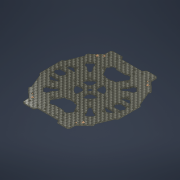
# Autodesk Inventor part: Lower Base fix 2
Saved by Autodesk Inventor 2021 (Build 250183000, 183)
## iProperties
Created: 2021-04-04
Part Number: Lower Base fix 2
Material: Fiberglass Batt
Document SubType Name: Modeling
Designer: ACER
Density: 0.032 g/cm^3
Appearance: Carbon Fiber 1
Author: ACER
Autodesk Inventor part; units mm, degrees
sketch "Sketch1" plane through (0, 0, 0) normal (0, 1, 0) x (-1, 0, 0)
  arc A0 (303.2496, 232.6894) -> (303.2496, 235.8894) centre (303.2496, 234.2894) ccw
  line L0 (323.663, 256.7678) -> (315.419, 242.7086)
  arc A1 (314.1875, 241.9686) -> (315.419, 242.7086) centre (314.125, 243.4673) ccw
  circle A2 centre (320.9996, 225.0394) radius 1.6
  line L1 (314.1875, 241.9686) -> (309.569, 241.7763)
  line L2 (309.569, 241.7763) -> (308.77, 240.8828)
  arc A3 (307.2791, 240.2159) -> (308.77, 240.8828) centre (307.2791, 242.2159) ccw
  line L3 (307.2791, 240.2159) -> (303.2192, 240.2159)
  line L4 (314.2761, 265.6643) -> (317.6382, 265.6643)
  arc A4 (314.2761, 265.6643) -> (312.529, 264.8601) centre (314.2761, 263.3643) ccw
  line L5 (303.2192, 263.7806) -> (311.6046, 263.7806)
  line L6 (311.6046, 263.7806) -> (312.529, 264.8601)
  arc A5 (332.5996, 207.2894) -> (329.3996, 207.2894) centre (330.9996, 207.2894) ccw
  line L7 (352.3567, 213.4142) -> (363.3075, 213.4142)
  line L8 (350.9567, 210.9441) -> (350.9567, 212.0142)
  line L9 (364.7075, 212.0142) -> (364.7075, 210.8124)
  line L10 (364.7075, 210.8124) -> (366.1742, 209.8202)
  line L11 (349.4293, 209.7993) -> (350.9567, 210.9441)
  arc A6 (366.7898, 208.6606) -> (366.1742, 209.8202) centre (365.3898, 208.6606) ccw
  line L12 (366.7898, 208.6606) -> (366.7898, 207.2894)
  arc A7 (349.4293, 209.7993) -> (348.8689, 208.679) centre (350.2689, 208.679) ccw
  line L13 (348.8689, 207.2894) -> (348.8689, 208.679)
  arc A8 (346.3456, 207.2894) -> (344.1536, 207.2894) centre (345.2496, 207.2894) ccw
  arc A9 (352.3567, 213.4142) -> (350.9567, 212.0142) centre (352.3567, 212.0142) ccw
  circle A10 centre (325.2496, 253.2894) radius 1.5
  arc A11 (323.663, 256.7678) -> (323.5245, 259.3038) centre (321.679, 257.9312) ccw
  line L14 (319.4837, 264.7369) -> (323.5245, 259.3038)
  arc A12 (319.4837, 264.7369) -> (317.6382, 265.6643) centre (317.6382, 263.3643) ccw
  line L15 (338.5006, 237.402) -> (338.4992, 237.3504)
  arc A13 (344.0065, 240.2975) -> (345.0316, 240.2557) centre (344.5587, 241.2489) ccw
  arc A14 (344.0065, 240.2975) -> (343.3339, 240.3141) centre (343.6551, 239.6921) ccw
  line L16 (343.3339, 240.3141) -> (338.8786, 238.0137)
  arc A15 (338.8786, 238.0137) -> (338.4997, 237.3913) centre (339.1997, 237.3917) ccw
  arc A16 (337.6845, 236.0559) -> (338.4997, 237.3913) centre (336.9997, 237.3905) ccw
  line L17 (337.6845, 236.0559) -> (333.2693, 233.7905)
  arc A17 (330.511, 234.5509) -> (330.7655, 234.3663) centre (331.2181, 235.258) ccw
  line L18 (331.9055, 233.7876) -> (330.7655, 234.3663)
  arc A18 (331.9055, 233.7876) -> (333.2693, 233.7905) centre (332.5845, 235.1251) ccw
  circle A19 centre (349.2496, 266.0394) radius 1.5
  circle A20 centre (342.7496, 272.2894) radius 1.5
  line L19 (345.8396, 249.7893) -> (348.5507, 247.0628)
  arc A21 (348.9285, 245.7899) -> (348.5507, 247.0628) centre (347.558, 246.0756) ccw
  line L20 (348.9285, 245.7899) -> (348.1581, 242.0944)
  arc A22 (347.7189, 241.5354) -> (348.1581, 242.0944) centre (347.375, 242.2577) ccw
  line L21 (347.7189, 241.5354) -> (345.0316, 240.2557)
  circle A23 centre (364.7496, 215.5394) radius 1.6
  arc A24 (364.7075, 212.0142) -> (363.3075, 213.4142) centre (363.3075, 212.0142) ccw
  circle A25 centre (349.2496, 229.2894) radius 1.5
  arc A26 (345.5474, 223.4422) -> (346.3385, 220.4514) centre (346.3385, 222.0514) ccw
  line L22 (346.3385, 220.4514) -> (360.2389, 220.4514)
  arc A27 (360.2389, 220.4514) -> (361.2146, 223.3195) centre (360.2389, 222.0514) ccw
  line L23 (353.0198, 227.6924) -> (345.5474, 223.4422)
  arc A28 (355.7803, 227.5007) -> (353.0198, 227.6924) centre (354.2558, 225.5193) ccw
  line L24 (361.2146, 223.3195) -> (355.7803, 227.5007)
  circle A29 centre (371.2496, 218.2894) radius 1.35
  circle A30 centre (318.9996, 271.2894) radius 1.5
  circle A31 centre (326.2496, 279.2894) radius 1.5
  circle A32 centre (313.2496, 278.5394) radius 1.5
  circle A33 centre (340.2496, 279.2894) radius 1.5
  line L25 (322.7496, 288.2894) -> (342.7496, 288.2894) construction
  arc A34 (307.2496, 207.2894) -> (303.2496, 211.2894) centre (303.2496, 207.2894) ccw
  arc A35 (310.6109, 212.4674) -> (308.4393, 214.6424) centre (303.2496, 207.2894) ccw
  arc A36 (322.7299, 215.1328) -> (311.2084, 226.7229) centre (303.2496, 207.2894) ccw
  line L26 (320.7332, 211.9779) -> (312.629, 211.4948)
  line L27 (307.4713, 216.6838) -> (308.0424, 224.7567)
  arc A37 (310.6109, 212.4674) -> (312.629, 211.4948) centre (312.4921, 213.7907) ccw
  arc A38 (307.4713, 216.6838) -> (308.4393, 214.6424) centre (309.7656, 216.5215) ccw
  arc A39 (311.2084, 226.7229) -> (308.0424, 224.7567) centre (310.3367, 224.5944) ccw
  arc A40 (320.7332, 211.9779) -> (322.7299, 215.1328) centre (320.5963, 214.2738) ccw
  line L28 (303.2496, 207.2894) -> (330.9996, 207.2894)
  line L29 (320.9996, 207.2894) -> (320.9996, 205.9182)
  line L30 (320.9996, 207.2894) -> (320.9996, 225.0394)
  line L31 (320.9996, 225.0394) -> (303.2496, 225.0394)
  line L32 (303.2496, 234.2894) -> (303.2496, 207.2894)
  line L33 (303.2496, 207.2894) -> (374.7496, 207.2894)
  line L34 (303.2496, 207.2894) -> (303.2496, 283.2894)
  line L35 (303.2496, 207.2894) -> (379.2496, 207.2894) construction
  line L36 (303.2496, 283.2894) -> (303.2496, 288.2894)
  line L37 (303.2496, 283.2894) -> (308.2496, 283.2894) construction
  line L38 (325.2496, 288.2894) -> (322.2496, 283.2894)
  line L39 (325.2496, 288.2894) -> (345.2496, 288.2894)
  line L40 (345.2496, 288.2894) -> (345.2496, 276.2894)
  line L41 (352.9139, 268.8587) -> (346.4139, 275.1087)
  line L42 (345.2496, 276.2894) -> (363.2694, 258.9607)
  line L43 (345.2496, 276.2894) -> (370.2496, 276.2894) construction
  line L44 (363.2694, 258.9607) -> (360.4968, 256.0775)
  line L45 (374.7496, 207.2894) -> (374.7496, 228.7894)
  line L46 (374.7496, 228.7894) -> (371.7496, 228.7894)
  line L47 (371.7496, 228.7894) -> (360.4968, 256.0775)
  line L48 (303.2496, 207.2894) -> (320.9996, 225.0394)
  line L49 (303.2496, 207.2894) -> (328.3519, 207.2894) construction
  line L50 (303.2496, 207.2894) -> (389.5844, 207.2894) construction
  line L51 (345.7947, 249.8345) -> (345.8396, 249.7893)
  line L52 (336.2743, 247.3737) -> (333.9739, 242.9184)
  arc A41 (333.3515, 242.5395) -> (333.9739, 242.9184) centre (333.3519, 243.2395) ccw
  line L53 (333.3622, 242.5404) -> (333.3106, 242.539)
  arc A42 (333.3515, 242.5395) -> (332.0161, 241.7243) centre (333.3507, 241.0395) ccw
  arc A43 (330.3265, 234.8053) -> (330.511, 234.5509) centre (331.2181, 235.258) ccw
  line L54 (329.7477, 235.9453) -> (330.3265, 234.8053)
  arc A44 (329.7507, 237.3091) -> (329.7477, 235.9453) centre (331.0853, 236.6243) ccw
  line L55 (332.0161, 241.7243) -> (329.7507, 237.3091)
  arc A45 (336.2159, 249.0714) -> (336.2577, 248.0463) centre (337.2091, 248.5985) ccw
  arc A46 (336.2743, 247.3737) -> (336.2577, 248.0463) centre (335.6523, 247.6949) ccw
  line L56 (345.7495, 249.8794) -> (343.023, 252.5905)
  arc A47 (343.023, 252.5905) -> (341.7501, 252.9683) centre (342.0358, 251.5978) ccw
  line L57 (341.7501, 252.9683) -> (338.0546, 252.1979)
  arc A48 (338.0546, 252.1979) -> (337.4956, 251.7587) centre (338.2179, 251.4148) ccw
  line L58 (337.4956, 251.7587) -> (336.2159, 249.0714)
  line L59 (345.7947, 249.8345) -> (345.7495, 249.8794)
  line L60 (303.2496, 283.2894) -> (322.2496, 283.2894)
  line L61 (303.2496, 283.2894) -> (322.2496, 283.2894)
  line L62 (322.2496, 283.2894) -> (325.2496, 288.2894)
  line L63 (325.2496, 288.2894) -> (345.2496, 288.2894)
  line L64 (345.2496, 288.2894) -> (345.2496, 276.2894)
  line L65 (345.2496, 276.2894) -> (363.2694, 258.9607)
  line L66 (363.2694, 258.9607) -> (360.4968, 256.0775)
  line L67 (360.4968, 256.0775) -> (371.7496, 228.7894)
  line L68 (371.7496, 228.7894) -> (374.7496, 228.7894)
  line L69 (374.7496, 228.7894) -> (374.7496, 207.2894)
  line L70 (374.7496, 207.2894) -> (303.2496, 207.2894)
  arc A49 (124.9548, 185.5697) -> (124.3945, 184.4495) centre (125.7945, 184.4495) ccw
  line L71 (124.3945, 183.0599) -> (124.3945, 184.4495)
  arc A50 (121.8711, 183.0599) -> (119.6792, 183.0599) centre (120.7752, 183.0599) ccw
  line L72 (140.2331, 187.7846) -> (140.2331, 186.5829)
  line L73 (140.2331, 186.5829) -> (141.6998, 185.5907)
  circle A51 centre (140.2752, 191.3099) radius 1.6
  arc A52 (140.2331, 187.7846) -> (138.8331, 189.1846) centre (138.8331, 187.7846) ccw
  arc A53 (142.3153, 184.4311) -> (141.6998, 185.5907) centre (140.9153, 184.4311) ccw
  circle A54 centre (146.7752, 194.0599) radius 1.35
  line L74 (142.3153, 184.4311) -> (142.3153, 183.0599)
  line L75 (127.8822, 189.1846) -> (138.8331, 189.1846)
  line L76 (126.4822, 186.7146) -> (126.4822, 187.7846)
  line L77 (124.9548, 185.5697) -> (126.4822, 186.7146)
  arc A55 (135.7645, 196.2219) -> (136.7402, 199.09) centre (135.7645, 197.8219) ccw
  arc A56 (127.8822, 189.1846) -> (126.4822, 187.7846) centre (127.8822, 187.7846) ccw
  line L78 (136.7402, 199.09) -> (131.3058, 203.2711)
  arc A57 (131.3058, 203.2711) -> (128.5453, 203.4628) centre (129.7814, 201.2897) ccw
  line L79 (121.864, 196.2219) -> (135.7645, 196.2219)
  arc A58 (121.073, 199.2126) -> (121.864, 196.2219) centre (121.864, 197.8219) ccw
  line L80 (128.5453, 203.4628) -> (121.073, 199.2126)
  circle A59 centre (124.7752, 205.0599) radius 1.5
  circle A60 centre (96.5252, 200.8099) radius 1.6
  line L81 (118.8595, 216.0846) -> (114.4041, 213.7841)
  arc A61 (114.4041, 213.7841) -> (114.0253, 213.1618) centre (114.7253, 213.1622) ccw
  line L82 (114.0261, 213.1725) -> (114.0247, 213.1209)
  arc A62 (113.21, 211.8264) -> (114.0253, 213.1618) centre (112.5253, 213.1609) ccw
  arc A63 (106.0366, 210.3213) -> (106.2911, 210.1367) centre (106.7437, 211.0284) ccw
  line L83 (107.4311, 209.558) -> (106.2911, 210.1367)
  arc A64 (107.4311, 209.558) -> (108.7948, 209.561) centre (108.1101, 210.8955) ccw
  line L84 (113.21, 211.8264) -> (108.7948, 209.561)
  arc A65 (78.7752, 208.4599) -> (78.7752, 211.6599) centre (78.7752, 210.0599) ccw
  arc A66 (89.713, 217.7391) -> (90.9446, 218.479) centre (89.6506, 219.2378) ccw
  line L85 (89.713, 217.7391) -> (85.0945, 217.5467)
  line L86 (85.0945, 217.5467) -> (84.2956, 216.6532)
  arc A67 (82.8047, 215.9864) -> (84.2956, 216.6532) centre (82.8047, 217.9864) ccw
  line L87 (82.8047, 215.9864) -> (78.7448, 215.9864)
  arc A68 (119.532, 216.068) -> (120.5572, 216.0262) centre (120.0842, 217.0193) ccw
  arc A69 (119.532, 216.068) -> (118.8595, 216.0846) centre (119.1806, 215.4626) ccw
  circle A70 centre (124.7752, 241.8099) radius 1.5
  line L88 (121.3651, 225.5598) -> (124.0763, 222.8332)
  arc A71 (124.4541, 221.5604) -> (124.0763, 222.8332) centre (123.0835, 221.8461) ccw
  line L89 (124.4541, 221.5604) -> (123.6837, 217.8649)
  arc A72 (123.2445, 217.3059) -> (123.6837, 217.8649) centre (122.9005, 218.0281) ccw
  line L90 (123.2445, 217.3059) -> (120.5572, 216.0262)
  line L91 (99.1886, 232.5383) -> (90.9446, 218.479)
  arc A73 (95.0093, 240.5073) -> (93.1637, 241.4347) centre (93.1637, 239.1347) ccw
  line L92 (89.8016, 241.4347) -> (93.1637, 241.4347)
  line L93 (95.0093, 240.5073) -> (99.0501, 235.0743)
  arc A74 (99.1886, 232.5383) -> (99.0501, 235.0743) centre (97.2045, 233.7017) ccw
  circle A75 centre (100.7752, 229.0599) radius 1.5
  line L94 (87.1302, 239.551) -> (88.0545, 240.6306)
  arc A76 (89.8016, 241.4347) -> (88.0545, 240.6306) centre (89.8016, 239.1347) ccw
  circle A77 centre (94.5252, 247.0599) radius 1.5
  circle A78 centre (101.7752, 255.0599) radius 1.5
  circle A79 centre (118.2752, 248.0599) radius 1.5
  circle A80 centre (115.7752, 255.0599) radius 1.5
  line L95 (78.7448, 239.551) -> (87.1302, 239.551)
  circle A81 centre (88.7752, 254.3099) radius 1.5
  arc A82 (86.1364, 188.2379) -> (83.9649, 190.4129) centre (78.7752, 183.0599) ccw
  arc A83 (98.2554, 190.9033) -> (86.7339, 202.4933) centre (78.7752, 183.0599) ccw
  line L96 (96.2587, 187.7483) -> (88.1545, 187.2652)
  line L97 (82.9969, 192.4543) -> (83.568, 200.5272)
  arc A84 (86.1364, 188.2379) -> (88.1545, 187.2652) centre (88.0177, 189.5611) ccw
  arc A85 (82.9969, 192.4543) -> (83.9649, 190.4129) centre (85.2912, 192.292) ccw
  arc A86 (86.7339, 202.4933) -> (83.568, 200.5272) centre (85.8622, 200.3649) ccw
  arc A87 (96.2587, 187.7483) -> (98.2554, 190.9033) centre (96.1219, 190.0442) ccw
  line L98 (121.3203, 225.605) -> (121.3651, 225.5598)
  line L99 (121.3203, 225.605) -> (121.2751, 225.6499)
  line L100 (121.2751, 225.6499) -> (118.5485, 228.361)
  line L101 (117.2757, 228.7388) -> (113.5802, 227.9684)
  arc A88 (118.5485, 228.361) -> (117.2757, 228.7388) centre (117.5614, 227.3682) ccw
  arc A89 (111.7415, 224.8419) -> (111.7833, 223.8167) centre (112.7346, 224.3689) ccw
  arc A90 (111.7998, 223.1442) -> (111.7833, 223.8167) centre (111.1779, 223.4653) ccw
  arc A91 (113.5802, 227.9684) -> (113.0212, 227.5292) centre (113.7434, 227.1852) ccw
  line L102 (113.0212, 227.5292) -> (111.7415, 224.8419)
  line L103 (111.7998, 223.1442) -> (109.4994, 218.6888)
  arc A92 (108.8771, 218.31) -> (109.4994, 218.6888) centre (108.8774, 219.01) ccw
  line L104 (108.8878, 218.3108) -> (108.8362, 218.3094)
  arc A93 (108.8771, 218.31) -> (107.5416, 217.4947) centre (108.8762, 216.81) ccw
  line L105 (107.5416, 217.4947) -> (105.2763, 213.0795)
  arc A94 (105.2763, 213.0795) -> (105.2733, 211.7158) centre (106.6108, 212.3948) ccw
  line L106 (105.2733, 211.7158) -> (105.852, 210.5758)
  arc A95 (105.852, 210.5758) -> (106.0366, 210.3213) centre (106.7437, 211.0284) ccw
  line L107 (78.7752, 259.0599) -> (97.7752, 259.0599)
  line L108 (97.7752, 259.0599) -> (100.7752, 264.0599)
  line L109 (100.7752, 264.0599) -> (120.7752, 264.0599)
  line L110 (120.7752, 264.0599) -> (120.7752, 252.0599)
  line L111 (120.7752, 252.0599) -> (138.795, 234.7311)
  line L112 (138.795, 234.7311) -> (136.0224, 231.8479)
  line L113 (136.0224, 231.8479) -> (147.2752, 204.5599)
  line L114 (147.2752, 204.5599) -> (150.2752, 204.5599)
  line L115 (150.2752, 204.5599) -> (150.2752, 183.0599)
  arc A96 (108.1252, 183.0599) -> (104.9252, 183.0599) centre (106.5252, 183.0599) ccw
  line L116 (127.8822, 176.9351) -> (138.8331, 176.9351)
  line L117 (121.864, 169.8979) -> (135.7645, 169.8979)
  arc A97 (126.4822, 178.3351) -> (127.8822, 176.9351) centre (127.8822, 178.3351) ccw
  line L118 (126.4822, 179.4051) -> (126.4822, 178.3351)
  arc A98 (124.3945, 181.6703) -> (124.9548, 180.55) centre (125.7945, 181.6703) ccw
  line L119 (124.3945, 183.0599) -> (124.3945, 181.6703)
  line L120 (124.9548, 180.55) -> (126.4822, 179.4051)
  line L121 (140.2331, 178.3351) -> (140.2331, 179.5369)
  arc A99 (138.8331, 176.9351) -> (140.2331, 178.3351) centre (138.8331, 178.3351) ccw
  line L122 (142.3153, 181.6887) -> (142.3153, 183.0599)
  line L123 (140.2331, 179.5369) -> (141.6998, 180.5291)
  circle A100 centre (140.2752, 174.8099) radius 1.6
  circle A101 centre (146.7752, 172.0599) radius 1.35
  arc A102 (141.6998, 180.5291) -> (142.3153, 181.6887) centre (140.9153, 181.6887) ccw
  arc A103 (78.7752, 154.4599) -> (78.7752, 157.6599) centre (78.7752, 156.0599) ccw
  arc A104 (90.9446, 147.6407) -> (89.713, 148.3807) centre (89.6506, 146.882) ccw
  arc A105 (83.568, 165.5926) -> (86.7339, 163.6264) centre (85.8622, 165.7549) ccw
  line L124 (82.8047, 150.1334) -> (78.7448, 150.1334)
  line L125 (89.713, 148.3807) -> (85.0945, 148.573)
  arc A106 (84.2956, 149.4665) -> (82.8047, 150.1334) centre (82.8047, 148.1334) ccw
  line L126 (85.0945, 148.573) -> (84.2956, 149.4665)
  line L127 (136.7402, 167.0298) -> (131.3058, 162.8486)
  arc A107 (128.5453, 162.6569) -> (131.3058, 162.8486) centre (129.7814, 164.83) ccw
  arc A108 (121.864, 169.8979) -> (121.073, 166.9071) centre (121.864, 168.2979) ccw
  line L128 (128.5453, 162.6569) -> (121.073, 166.9071)
  circle A109 centre (124.7752, 161.0599) radius 1.5
  line L129 (121.3651, 140.56) -> (124.0763, 143.2865)
  arc A110 (118.8595, 150.0352) -> (119.532, 150.0518) centre (119.1806, 150.6572) ccw
  line L130 (124.4541, 144.5594) -> (123.6837, 148.2549)
  arc A111 (120.5572, 150.0936) -> (119.532, 150.0518) centre (120.0842, 149.1004) ccw
  arc A112 (123.6837, 148.2549) -> (123.2445, 148.8139) centre (122.9005, 148.0916) ccw
  line L131 (123.2445, 148.8139) -> (120.5572, 150.0936)
  line L132 (99.1886, 133.5815) -> (90.9446, 147.6407)
  circle A113 centre (100.7752, 137.0599) radius 1.5
  arc A114 (99.0501, 131.0455) -> (99.1886, 133.5815) centre (97.2045, 132.4181) ccw
  line L133 (95.0093, 125.6124) -> (99.0501, 131.0455)
  arc A115 (93.1637, 124.685) -> (95.0093, 125.6124) centre (93.1637, 126.985) ccw
  line L134 (89.8016, 124.685) -> (93.1637, 124.685)
  line L135 (78.7448, 126.5687) -> (87.1302, 126.5687)
  line L136 (87.1302, 126.5687) -> (88.0545, 125.4892)
  arc A116 (88.0545, 125.4892) -> (89.8016, 124.685) centre (89.8016, 126.985) ccw
  circle A117 centre (94.5252, 119.0599) radius 1.5
  circle A118 centre (88.7752, 111.8099) radius 1.5
  circle A119 centre (96.5252, 165.3099) radius 1.6
  line L137 (82.9969, 173.6655) -> (83.568, 165.5926)
  arc A120 (83.9649, 175.7069) -> (82.9969, 173.6655) centre (85.2912, 173.8278) ccw
  arc A121 (83.9649, 175.7069) -> (86.1364, 177.8819) centre (78.7752, 183.0599) ccw
  arc A122 (88.1545, 178.8545) -> (86.1364, 177.8819) centre (88.0177, 176.5586) ccw
  arc A123 (86.7339, 163.6264) -> (98.2554, 175.2165) centre (78.7752, 183.0599) ccw
  arc A124 (119.6792, 183.0599) -> (121.8711, 183.0599) centre (120.7752, 183.0599) ccw
  arc A125 (98.2554, 175.2165) -> (96.2587, 178.3714) centre (96.1219, 176.0755) ccw
  line L138 (96.2587, 178.3714) -> (88.1545, 178.8545)
  arc A126 (114.0253, 152.958) -> (114.4041, 152.3356) centre (114.7253, 152.9576) ccw
  line L139 (114.0261, 152.9473) -> (114.0247, 152.9988)
  arc A127 (114.0253, 152.958) -> (113.21, 154.2934) centre (112.5253, 152.9588) ccw
  arc A128 (106.2911, 155.983) -> (106.0366, 155.7984) centre (106.7437, 155.0913) ccw
  line L140 (107.4311, 156.5617) -> (106.2911, 155.983)
  arc A129 (108.7948, 156.5588) -> (107.4311, 156.5617) centre (108.1101, 155.2242) ccw
  line L141 (113.21, 154.2934) -> (108.7948, 156.5588)
  arc A130 (105.2733, 154.404) -> (105.2763, 153.0402) centre (106.6108, 153.725) ccw
  arc A131 (106.0366, 155.7984) -> (105.852, 155.544) centre (106.7437, 155.0913) ccw
  line L142 (105.2733, 154.404) -> (105.852, 155.544)
  line L143 (107.5416, 148.625) -> (105.2763, 153.0402)
  arc A132 (136.7402, 167.0298) -> (135.7645, 169.8979) centre (135.7645, 168.2979) ccw
  line L144 (121.3203, 140.5148) -> (121.3651, 140.56)
  line L145 (121.3203, 140.5148) -> (121.2751, 140.4699)
  line L146 (118.8595, 150.0352) -> (114.4041, 152.3356)
  line L147 (121.2751, 140.4699) -> (118.5485, 137.7588)
  arc A133 (107.5416, 148.625) -> (108.8771, 147.8098) centre (108.8762, 149.3098) ccw
  arc A134 (109.4994, 147.4309) -> (108.8771, 147.8098) centre (108.8774, 147.1098) ccw
  line L148 (108.8878, 147.8089) -> (108.8362, 147.8103)
  arc A135 (117.2757, 137.381) -> (118.5485, 137.7588) centre (117.5614, 138.7515) ccw
  line L149 (117.2757, 137.381) -> (113.5802, 138.1514)
  circle A136 centre (101.7752, 111.0599) radius 1.5
  circle A137 centre (115.7752, 111.0599) radius 1.5
  circle A138 centre (124.7752, 124.3099) radius 1.5
  arc A139 (124.0763, 143.2865) -> (124.4541, 144.5594) centre (123.0835, 144.2736) ccw
  circle A140 centre (118.2752, 118.0599) radius 1.5
  line L150 (111.7998, 142.9756) -> (109.4994, 147.4309)
  arc A141 (111.7833, 142.303) -> (111.7998, 142.9756) centre (111.1779, 142.6544) ccw
  arc A142 (111.7833, 142.303) -> (111.7415, 141.2779) centre (112.7346, 141.7508) ccw
  line L151 (113.0212, 138.5906) -> (111.7415, 141.2779)
  arc A143 (113.0212, 138.5906) -> (113.5802, 138.1514) centre (113.7434, 138.9345) ccw
  line L152 (78.7752, 107.0599) -> (97.7752, 107.0599)
  line L153 (97.7752, 107.0599) -> (100.7752, 102.0599)
  line L154 (100.7752, 102.0599) -> (120.7752, 102.0599)
  line L155 (120.7752, 102.0599) -> (120.7752, 114.0599)
  line L156 (120.7752, 114.0599) -> (138.795, 131.3886)
  line L157 (138.795, 131.3886) -> (136.0224, 134.2718)
  line L158 (136.0224, 134.2718) -> (147.2752, 161.5599)
  line L159 (147.2752, 161.5599) -> (150.2752, 161.5599)
  line L160 (150.2752, 161.5599) -> (150.2752, 183.0599)
  arc A144 (104.9252, 183.0599) -> (108.1252, 183.0599) centre (106.5252, 183.0599) ccw
  line L161 (29.6681, 189.1846) -> (18.7172, 189.1846)
  line L162 (35.6863, 196.2219) -> (21.7858, 196.2219)
  arc A145 (31.0681, 187.7846) -> (29.6681, 189.1846) centre (29.6681, 187.7846) ccw
  line L163 (31.0681, 186.7146) -> (31.0681, 187.7846)
  arc A146 (33.1558, 184.4495) -> (32.5955, 185.5697) centre (31.7558, 184.4495) ccw
  line L164 (33.1558, 183.0599) -> (33.1558, 184.4495)
  line L165 (32.5955, 185.5697) -> (31.0681, 186.7146)
  line L166 (17.3172, 187.7846) -> (17.3172, 186.5829)
  arc A147 (18.7172, 189.1846) -> (17.3172, 187.7846) centre (18.7172, 187.7846) ccw
  line L167 (15.235, 184.4311) -> (15.235, 183.0599)
  line L168 (17.3172, 186.5829) -> (15.8505, 185.5907)
  circle A148 centre (17.2752, 191.3099) radius 1.6
  circle A149 centre (10.7752, 194.0599) radius 1.35
  arc A150 (15.8505, 185.5907) -> (15.235, 184.4311) centre (16.635, 184.4311) ccw
  arc A151 (78.7752, 211.6599) -> (78.7752, 208.4599) centre (78.7752, 210.0599) ccw
  arc A152 (66.6058, 218.479) -> (67.8373, 217.7391) centre (67.8997, 219.2378) ccw
  arc A153 (73.9823, 200.5272) -> (70.8164, 202.4933) centre (71.6881, 200.3649) ccw
  line L169 (74.7456, 215.9864) -> (78.8055, 215.9864)
  line L170 (67.8373, 217.7391) -> (72.4558, 217.5467)
  arc A154 (73.2547, 216.6532) -> (74.7456, 215.9864) centre (74.7456, 217.9864) ccw
  line L171 (72.4558, 217.5467) -> (73.2547, 216.6532)
  line L172 (20.8102, 199.09) -> (26.2445, 203.2711)
  arc A155 (29.005, 203.4628) -> (26.2445, 203.2711) centre (27.769, 201.2897) ccw
  arc A156 (35.6863, 196.2219) -> (36.4774, 199.2126) centre (35.6863, 197.8219) ccw
  line L173 (29.005, 203.4628) -> (36.4774, 199.2126)
  circle A157 centre (32.7752, 205.0599) radius 1.5
  line L174 (36.1852, 225.5598) -> (33.474, 222.8332)
  arc A158 (38.6908, 216.0846) -> (38.0183, 216.068) centre (38.3697, 215.4626) ccw
  line L175 (33.0963, 221.5604) -> (33.8666, 217.8649)
  arc A159 (36.9931, 216.0262) -> (38.0183, 216.068) centre (37.4661, 217.0193) ccw
  arc A160 (33.8666, 217.8649) -> (34.3058, 217.3059) centre (34.6498, 218.0281) ccw
  line L176 (34.3058, 217.3059) -> (36.9931, 216.0262)
  line L177 (58.3617, 232.5383) -> (66.6058, 218.479)
  circle A161 centre (56.7752, 229.0599) radius 1.5
  arc A162 (58.5002, 235.0743) -> (58.3617, 232.5383) centre (60.3458, 233.7017) ccw
  line L178 (62.541, 240.5073) -> (58.5002, 235.0743)
  arc A163 (64.3866, 241.4347) -> (62.541, 240.5073) centre (64.3866, 239.1347) ccw
  line L179 (67.7487, 241.4347) -> (64.3866, 241.4347)
  line L180 (78.8055, 239.551) -> (70.4201, 239.551)
  line L181 (70.4201, 239.551) -> (69.4958, 240.6306)
  arc A164 (69.4958, 240.6306) -> (67.7487, 241.4347) centre (67.7487, 239.1347) ccw
  circle A165 centre (63.0252, 247.0599) radius 1.5
  circle A166 centre (68.7752, 254.3099) radius 1.5
  circle A167 centre (61.0252, 200.8099) radius 1.6
  line L182 (74.5534, 192.4543) -> (73.9823, 200.5272)
  arc A168 (73.5854, 190.4129) -> (74.5534, 192.4543) centre (72.2591, 192.292) ccw
  arc A169 (73.5854, 190.4129) -> (71.4139, 188.2379) centre (78.7752, 183.0599) ccw
  arc A170 (69.3958, 187.2652) -> (71.4139, 188.2379) centre (69.5327, 189.5611) ccw
  arc A171 (70.8164, 202.4933) -> (59.2949, 190.9033) centre (78.7752, 183.0599) ccw
  arc A172 (37.8711, 183.0599) -> (35.6792, 183.0599) centre (36.7752, 183.0599) ccw
  arc A173 (59.2949, 190.9033) -> (61.2916, 187.7483) centre (61.4284, 190.0442) ccw
  line L183 (61.2916, 187.7483) -> (69.3958, 187.2652)
  arc A174 (43.525, 213.1618) -> (43.1462, 213.7841) centre (42.825, 213.1622) ccw
  line L184 (43.5242, 213.1725) -> (43.5256, 213.1209)
  arc A175 (43.525, 213.1618) -> (44.3403, 211.8264) centre (45.025, 213.1609) ccw
  arc A176 (51.2593, 210.1367) -> (51.5137, 210.3213) centre (50.8066, 211.0284) ccw
  line L185 (50.1192, 209.558) -> (51.2593, 210.1367)
  arc A177 (48.7555, 209.561) -> (50.1192, 209.558) centre (49.4403, 210.8955) ccw
  line L186 (44.3403, 211.8264) -> (48.7555, 209.561)
  arc A178 (52.277, 211.7158) -> (52.2741, 213.0795) centre (50.9395, 212.3948) ccw
  arc A179 (51.5137, 210.3213) -> (51.6983, 210.5758) centre (50.8066, 211.0284) ccw
  line L187 (52.277, 211.7158) -> (51.6983, 210.5758)
  line L188 (50.0087, 217.4947) -> (52.2741, 213.0795)
  arc A180 (20.8102, 199.09) -> (21.7858, 196.2219) centre (21.7858, 197.8219) ccw
  line L189 (36.2301, 225.605) -> (36.1852, 225.5598)
  line L190 (36.2301, 225.605) -> (36.2753, 225.6499)
  line L191 (38.6908, 216.0846) -> (43.1462, 213.7841)
  line L192 (36.2753, 225.6499) -> (39.0018, 228.361)
  arc A181 (50.0087, 217.4947) -> (48.6733, 218.31) centre (48.6741, 216.81) ccw
  arc A182 (48.0509, 218.6888) -> (48.6733, 218.31) centre (48.6729, 219.01) ccw
  line L193 (48.6625, 218.3108) -> (48.7141, 218.3094)
  arc A183 (40.2746, 228.7388) -> (39.0018, 228.361) centre (39.9889, 227.3682) ccw
  line L194 (40.2746, 228.7388) -> (43.9701, 227.9684)
  circle A184 centre (55.7752, 255.0599) radius 1.5
  circle A185 centre (41.7752, 255.0599) radius 1.5
  circle A186 centre (32.7752, 241.8099) radius 1.5
  arc A187 (33.474, 222.8332) -> (33.0963, 221.5604) centre (34.4668, 221.8461) ccw
  circle A188 centre (39.2752, 248.0599) radius 1.5
  line L195 (45.7505, 223.1442) -> (48.0509, 218.6888)
  arc A189 (45.7671, 223.8167) -> (45.7505, 223.1442) centre (46.3725, 223.4653) ccw
  arc A190 (45.7671, 223.8167) -> (45.8088, 224.8419) centre (44.8157, 224.3689) ccw
  line L196 (44.5292, 227.5292) -> (45.8088, 224.8419)
  arc A191 (44.5292, 227.5292) -> (43.9701, 227.9684) centre (43.8069, 227.1852) ccw
  line L197 (78.7752, 259.0599) -> (59.7752, 259.0599)
  line L198 (59.7752, 259.0599) -> (56.7752, 264.0599)
  line L199 (56.7752, 264.0599) -> (36.7752, 264.0599)
  line L200 (36.7752, 264.0599) -> (36.7752, 252.0599)
  line L201 (36.7752, 252.0599) -> (18.7553, 234.7311)
  line L202 (18.7553, 234.7311) -> (21.5279, 231.8479)
  line L203 (21.5279, 231.8479) -> (10.2752, 204.5599)
  line L204 (10.2752, 204.5599) -> (7.2752, 204.5599)
  line L205 (7.2752, 204.5599) -> (7.2752, 183.0599)
  arc A192 (52.6252, 183.0599) -> (49.4252, 183.0599) centre (51.0252, 183.0599) ccw
  line L206 (10.2752, 161.5599) -> (7.2752, 161.5599)
  line L207 (21.5279, 134.2718) -> (10.2752, 161.5599)
  line L208 (15.235, 181.6887) -> (15.235, 183.0599)
  arc A193 (15.235, 181.6887) -> (15.8505, 180.5291) centre (16.635, 181.6887) ccw
  line L209 (17.3172, 178.3351) -> (17.3172, 179.5369)
  line L210 (17.3172, 179.5369) -> (15.8505, 180.5291)
  arc A194 (17.3172, 178.3351) -> (18.7172, 176.9351) centre (18.7172, 178.3351) ccw
  circle A195 centre (17.2752, 174.8099) radius 1.6
  circle A196 centre (10.7752, 172.0599) radius 1.35
  line L211 (20.8102, 167.0298) -> (26.2445, 162.8486)
  arc A197 (21.7858, 169.8979) -> (20.8102, 167.0298) centre (21.7858, 168.2979) ccw
  line L212 (7.2752, 161.5599) -> (7.2752, 183.0599)
  circle A198 centre (32.7752, 124.3099) radius 1.5
  line L213 (18.7553, 131.3886) -> (21.5279, 134.2718)
  line L214 (36.7752, 114.0599) -> (18.7553, 131.3886)
  circle A199 centre (39.2752, 118.0599) radius 1.5
  arc A200 (35.6792, 183.0599) -> (37.8711, 183.0599) centre (36.7752, 183.0599) ccw
  line L215 (33.1558, 183.0599) -> (33.1558, 181.6703)
  arc A201 (32.5955, 180.55) -> (33.1558, 181.6703) centre (31.7558, 181.6703) ccw
  line L216 (32.5955, 180.55) -> (31.0681, 179.4051)
  line L217 (31.0681, 179.4051) -> (31.0681, 178.3351)
  line L218 (35.6863, 169.8979) -> (21.7858, 169.8979)
  arc A202 (29.6681, 176.9351) -> (31.0681, 178.3351) centre (29.6681, 178.3351) ccw
  line L219 (36.2301, 140.5148) -> (36.1852, 140.56)
  line L220 (36.2301, 140.5148) -> (36.2753, 140.4699)
  line L221 (36.2753, 140.4699) -> (39.0018, 137.7588)
  arc A203 (39.0018, 137.7588) -> (40.2746, 137.381) centre (39.9889, 138.7515) ccw
  arc A204 (45.7505, 142.9756) -> (45.7671, 142.303) centre (46.3725, 142.6544) ccw
  arc A205 (45.8088, 141.2779) -> (45.7671, 142.303) centre (44.8157, 141.7508) ccw
  line L222 (40.2746, 137.381) -> (43.9701, 138.1514)
  arc A206 (43.9701, 138.1514) -> (44.5292, 138.5906) centre (43.8069, 138.9345) ccw
  line L223 (44.5292, 138.5906) -> (45.8088, 141.2779)
  arc A207 (26.2445, 162.8486) -> (29.005, 162.6569) centre (27.769, 164.83) ccw
  arc A208 (36.4774, 166.9071) -> (35.6863, 169.8979) centre (35.6863, 168.2979) ccw
  line L224 (29.005, 162.6569) -> (36.4774, 166.9071)
  circle A209 centre (32.7752, 161.0599) radius 1.5
  line L225 (43.5242, 152.9473) -> (43.5256, 152.9988)
  arc A210 (43.1462, 152.3356) -> (43.525, 152.958) centre (42.825, 152.9576) ccw
  line L226 (38.6908, 150.0352) -> (43.1462, 152.3356)
  line L227 (48.6625, 147.8089) -> (48.7141, 147.8103)
  arc A211 (48.6733, 147.8098) -> (48.0509, 147.4309) centre (48.6729, 147.1098) ccw
  line L228 (45.7505, 142.9756) -> (48.0509, 147.4309)
  arc A212 (44.3403, 154.2934) -> (43.525, 152.958) centre (45.025, 152.9588) ccw
  line L229 (44.3403, 154.2934) -> (48.7555, 156.5588)
  arc A213 (48.6733, 147.8098) -> (50.0087, 148.625) centre (48.6741, 149.3098) ccw
  line L230 (50.0087, 148.625) -> (52.2741, 153.0402)
  arc A214 (50.1192, 156.5617) -> (48.7555, 156.5588) centre (49.4403, 155.2242) ccw
  arc A215 (51.5137, 155.7984) -> (51.2593, 155.983) centre (50.8066, 155.0913) ccw
  arc A216 (52.2741, 153.0402) -> (52.277, 154.404) centre (50.9395, 153.725) ccw
  arc A217 (51.6983, 155.544) -> (51.5137, 155.7984) centre (50.8066, 155.0913) ccw
  line L231 (52.277, 154.404) -> (51.6983, 155.544)
  line L232 (50.1192, 156.5617) -> (51.2593, 155.983)
  circle A218 centre (41.7752, 111.0599) radius 1.5
  circle A219 centre (55.7752, 111.0599) radius 1.5
  line L233 (59.7752, 107.0599) -> (56.7752, 102.0599)
  line L234 (56.7752, 102.0599) -> (36.7752, 102.0599)
  line L235 (36.7752, 102.0599) -> (36.7752, 114.0599)
  arc A220 (67.8373, 148.3807) -> (66.6058, 147.6407) centre (67.8997, 146.882) ccw
  arc A221 (58.3617, 133.5815) -> (58.5002, 131.0455) centre (60.3458, 132.4181) ccw
  circle A222 centre (56.7752, 137.0599) radius 1.5
  line L236 (58.3617, 133.5815) -> (66.6058, 147.6407)
  line L237 (67.8373, 148.3807) -> (72.4558, 148.573)
  arc A223 (74.7456, 150.1334) -> (73.2547, 149.4665) centre (74.7456, 148.1334) ccw
  line L238 (72.4558, 148.573) -> (73.2547, 149.4665)
  arc A224 (78.7752, 157.6599) -> (78.7752, 154.4599) centre (78.7752, 156.0599) ccw
  arc A225 (70.8164, 163.6264) -> (73.9823, 165.5926) centre (71.6881, 165.7549) ccw
  line L239 (74.7456, 150.1334) -> (78.8055, 150.1334)
  line L240 (62.541, 125.6124) -> (58.5002, 131.0455)
  line L241 (70.4201, 126.5687) -> (69.4958, 125.4892)
  line L242 (67.7487, 124.685) -> (64.3866, 124.685)
  arc A226 (67.7487, 124.685) -> (69.4958, 125.4892) centre (67.7487, 126.985) ccw
  arc A227 (62.541, 125.6124) -> (64.3866, 124.685) centre (64.3866, 126.985) ccw
  line L243 (78.8055, 126.5687) -> (70.4201, 126.5687)
  circle A228 centre (63.0252, 119.0599) radius 1.5
  circle A229 centre (68.7752, 111.8099) radius 1.5
  line L244 (78.7752, 107.0599) -> (59.7752, 107.0599)
  line L245 (29.6681, 176.9351) -> (18.7172, 176.9351)
  line L246 (61.2916, 178.3714) -> (69.3958, 178.8545)
  arc A230 (49.4252, 183.0599) -> (52.6252, 183.0599) centre (51.0252, 183.0599) ccw
  line L247 (74.5534, 173.6655) -> (73.9823, 165.5926)
  arc A231 (59.2949, 175.2165) -> (70.8164, 163.6264) centre (78.7752, 183.0599) ccw
  arc A232 (74.5534, 173.6655) -> (73.5854, 175.7069) centre (72.2591, 173.8278) ccw
  arc A233 (61.2916, 178.3714) -> (59.2949, 175.2165) centre (61.4284, 176.0755) ccw
  arc A234 (71.4139, 177.8819) -> (73.5854, 175.7069) centre (78.7752, 183.0599) ccw
  arc A235 (71.4139, 177.8819) -> (69.3958, 178.8545) centre (69.5327, 176.5586) ccw
  circle A236 centre (61.0252, 165.3099) radius 1.6
  line L248 (36.1852, 140.56) -> (33.474, 143.2865)
  arc A237 (33.0963, 144.5594) -> (33.474, 143.2865) centre (34.4668, 144.2736) ccw
  arc A238 (38.0183, 150.0518) -> (38.6908, 150.0352) centre (38.3697, 150.6572) ccw
  arc A239 (38.0183, 150.0518) -> (36.9931, 150.0936) centre (37.4661, 149.1004) ccw
  line L249 (34.3058, 148.8139) -> (36.9931, 150.0936)
  arc A240 (34.3058, 148.8139) -> (33.8666, 148.2549) centre (34.6498, 148.0916) ccw
  line L250 (33.0963, 144.5594) -> (33.8666, 148.2549)
  circle A241 centre (78.7752, 183.0599) radius 4
  point P0 (0, 0)
  point P1 (307.3727, 215.2894)
  point P2 (311.2496, 211.4125)
  point P3 (323.6785, 212.1535)
  point P4 (308.2496, 227.6855)
  point P5 (338.6616, 237.2295)
  point P6 (303.2496, 240.2159)
  point P7 (303.2496, 225.0394)
  point P8 (308.0801, 225.0394)
  point P9 (314.4718, 225.0394)
  point P10 (319.3996, 225.0394)
  point P11 (320.9996, 223.4394)
  point P12 (320.9996, 218.5116)
  point P13 (320.9996, 212.0094)
  point P14 (303.2496, 263.7806)
  point P15 (82.8983, 191.0599)
  point P16 (86.7752, 187.183)
  point P17 (99.2041, 187.9239)
  point P18 (83.7752, 203.456)
  point P19 (82.8983, 175.0599)
  point P20 (86.7752, 178.9368)
  point P21 (83.7752, 162.6638)
  point P22 (99.2041, 178.1958)
  point P23 (74.6521, 191.0599)
  point P24 (70.7752, 187.183)
  point P25 (73.7752, 203.456)
  point P26 (58.3462, 187.9239)
  point P27 (58.3462, 178.1958)
  point P28 (70.7752, 178.9368)
  point P29 (73.7752, 162.6638)
  point P30 (74.6521, 175.0599)
  point P31 (43.525, 213.1618)
  point P32 (78.7752, 157.6599)
  point P33 (78.7752, 154.4599)
  dimension "d24" = 17.75
  dimension "d25" = 27.75
  dimension "d26" = 17.75
  dimension "d28" = 27
  dimension "d29" = 42
  dimension "d30" = 8.25
  dimension "d31" = 61.5
  dimension "d32" = 11
  dimension "d33" = 68
  dimension "d34" = 46
  dimension "d35" = 22
  dimension "d36" = 90
  dimension "d38" = 22
  dimension "d39" = 46
  dimension "d40" = 10
  dimension "d41" = 23
  dimension "d42" = 15.75
  dimension "d43" = 37
  dimension "d44" = 39.5
  dimension "d45" = 46
  dimension "d46" = 71.25
  dimension "d47" = 64
  dimension "d48" = 72
  dimension "d49" = 72
  dimension "d50" = 65
  dimension "d51" = 58.75
  dimension "d52" = 19
  dimension "d54" = 5
  dimension "d58" = 22
  dimension "d59" = 42
  dimension "d60" = 12
  dimension "d61" = 25
  dimension "d62" = 43.88
  dimension "d63" = 4
  dimension "d64" = 21.5
  dimension "d65" = 3
  dimension "d66" = 45
  dimension "d108" = 3.2
  dimension "d110" = 8
  constraints: 502 end point, 402 point on circle, 242 centre point, 27 point on line, 16 tangent, 11 horizontal, 7 collinear, 6 coincident, 6 equal radius, 5 perpendicular, 5 vertical, 4 equal length
  measures "d24" distance of L29.start L30.end
  measures "d25" distance of L28.end A35.centre
  measures "d26" distance of L30.end L31.end
  measures "d28" distance of L32.start L28.start
  measures "d29" distance of A34.centre A8.centre
  measures "d30" distance from line of L33 A23.centre
  measures "d31" distance from line of L32 A23.centre
  measures "d32" distance from line of A29.centre L33
  measures "d33" distance from line of L32 A29.centre
  measures "d34" distance from line of L32 A25.centre
  measures "d35" distance from line of L33 A25.centre
  measures "d36" angle of L35 L34
  measures "d38" distance from line of L34 A10.centre
  measures "d39" distance from line of L35 A10.centre
  measures "d40" distance from line of L34 A32.centre
  measures "d41" distance from line of L34 A31.centre
  measures "d42" distance from line of L34 A30.centre
  measures "d43" distance from line of L34 A33.centre
  measures "d44" distance from line of L34 A20.centre
  measures "d45" distance from line of L34 A19.centre
  measures "d46" distance from line of L28 A32.centre
  measures "d47" distance from line of L35 A30.centre
  measures "d48" distance from line of L35 A31.centre
  measures "d49" distance from line of L35 A33.centre
  measures "d50" distance from line of A20.centre L35
  measures "d51" distance from line of L35 A19.centre
  measures "d52" distance of L34.end L38.end
  measures "d54" distance of L34.end L36.end
  measures "d58" distance of L36.end L38.start
  measures "d59" distance of L36.end L39.end
  measures "d60" distance of L39.end L40.end
  measures "d61" distance of L40.end L42.end
  measures "d62" angle of L42 L43
  measures "d63" distance of L42.end L44.end
  measures "d64" distance of L33.end L45.end
  measures "d65" distance of L45.end L46.end
  measures "d66" angle of L49 L48
  measures "d108" diameter of A96
  measures "d110" diameter of A241
extrude "Extrusion1" add sketch "Sketch1" along normal blind 1.6 contours L107 L108 L109 L110 L111 L112 L113 L114 L115 L160 L159 L158 L157 L156 L155 L154 L153 L152 L244 L233 L234 L235 L214 L213 L207 L206 L212 L205 L204 L203 L202 L201 L200 L199 L198 L197
fillet "Fillet1" radius 1 4 edges at (-97.7752, 0.8, 259.0599) (-59.7752, 0.8, 259.0599) (-59.7752, 0.8, 107.0599) (-97.7752, 0.8, 107.0599)
fillet "Fillet2" radius 4 4 edges at (-36.7752, 0.8, 264.0599) (-120.7752, 0.8, 264.0599) (-36.7752, 0.8, 102.0599) (-120.7752, 0.8, 102.0599)
fillet "Fillet3" radius 3 4 edges at (-120.7752, 0.8, 252.0599) (-36.7752, 0.8, 252.0599) (-36.7752, 0.8, 114.0599) (-120.7752, 0.8, 114.0599)
fillet "Fillet4" radius 3 1 edges at (-138.795, 0.8, 234.7311)
fillet "Fillet5" radius 2 1 edges at (-136.0224, 0.8, 231.8479)
fillet "Fillet6" radius 2 1 edges at (-21.5279, 0.8, 231.8479)
fillet "Fillet7" radius 3 1 edges at (-18.7553, 0.8, 234.7311)
fillet "Fillet8" radius 3 2 edges at (-18.7553, 0.8, 131.3886) (-138.795, 0.8, 131.3886)
fillet "Fillet9" radius 2 2 edges at (-136.0224, 0.8, 134.2718) (-21.5279, 0.8, 134.2718)
fillet "Fillet10" radius 2 4 edges at (-147.2752, 0.8, 161.5599) (-147.2752, 0.8, 204.5599) (-10.2752, 0.8, 204.5599) (-10.2752, 0.8, 161.5599)
fillet "Fillet11" radius 3 4 edges at (-7.2752, 0.8, 161.5599) (-7.2752, 0.8, 204.5599) (-150.2752, 0.8, 204.5599) (-150.2752, 0.8, 161.5599)
ref_plane "Work Plane1" through (-39.2752, 0, 248.0599) normal (0.6931087, 0, 0.7208331) x (0.7208331, 0, -0.6931087)
ref_plane "Work Plane2" through (-32.7752, 1.6, 124.3099) normal (0.6931087, 0, -0.7208331) x (0, -1, 0)
ref_plane "Work Plane3" through (-124.7752, 0, 124.3099) normal (-0.6931087, 0, -0.7208331) x (0, 1, 0)
ref_plane "Work Plane4" through (-124.7752, 0, 241.8099) normal (-0.6931087, 0, 0.7208331) x (0.7208331, 0, 0.6931087)
body "Solid1"
